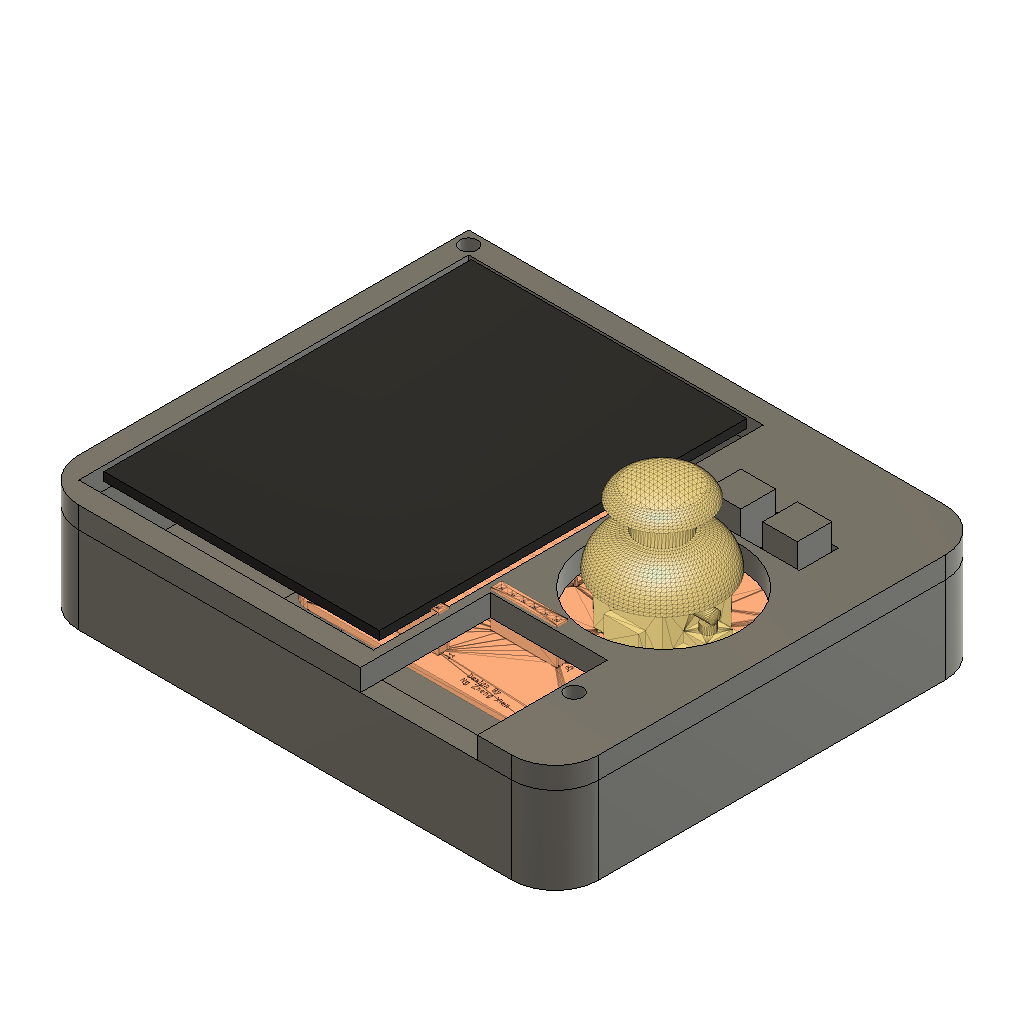
LastBraincellCase (Autodesk Fusion 360 design; units mm, degrees)
Autodesk Fusion 360 part; units mm, degrees
other "Base Mesh Feature1"
other "Base Mesh Feature2"
other "Modify1"
other "Modify2"
other "Modify3"
other "Modify4"
sketch "Sketch1" plane through (0, 0, 0) normal (0, 1, 0) x (1, 0, 0)
  line L0 (35.5, 33.5) -> (-32.6, 33.5)
  line L1 (-32.6, 33.5) -> (-32.6, -35)
  line L2 (-32.6, -35) -> (35.5, -35)
  line L3 (35.5, -35) -> (35.5, 33.5)
  line L4 (40.5, 38.5) -> (-37.6, 38.5)
  line L5 (-37.6, 38.5) -> (-37.6, -40)
  line L6 (-37.6, -40) -> (40.5, -40)
  line L7 (40.5, -40) -> (40.5, 38.5)
  line L8 (40.5, 38.5) -> (-37.6, -40) construction
  line L9 (-37.6, 38.5) -> (40.5, -40) construction
  circle A0 centre (-27.2012, -30.2516) radius 1.7516
  circle A1 centre (-27.2012, -30.2516) radius 2
  line L10 (-32.6, -35) -> (-24.6, -35)
  line L11 (-24.6, -35) -> (-24.6, -27)
  line L12 (-24.6, -27) -> (-32.6, -27)
  line L13 (-32.6, -27) -> (-32.6, -35)
  circle A2 centre (29.796, 15.5463) radius 1.7537
  circle A3 centre (29.796, 15.5463) radius 2
  line L14 (35.5, 19.9163) -> (25.5, 19.9163)
  line L15 (25.5, 19.9163) -> (25.5, 11.9163)
  line L16 (25.5, 11.9163) -> (35.5, 11.9163)
  line L17 (35.5, 11.9163) -> (35.5, 19.9163)
  line L18 (35.5, -35) -> (25.5, -35)
  line L19 (25.5, -35) -> (25.5, -27)
  line L20 (25.5, -27) -> (35.5, -27)
  line L21 (35.5, -27) -> (35.5, -35)
  circle A4 centre (29.6047, -30.2676) radius 1.7586
  circle A5 centre (29.6047, -30.2676) radius 2
  point P0 (1.45, -0.75)
  dimension "d1" = 78.1
  dimension "d2" = 78.5
  dimension "d3" = 4
  dimension "d4" = 8
  dimension "d5" = 8
  dimension "d6" = 4
  dimension "d7" = 10
  dimension "d8" = 8
  dimension "d9" = 10
  dimension "d10" = 8
  dimension "d11" = 4
  constraint horizontal L0
  constraint vertical L1
  constraint horizontal L2
  constraint vertical L3
  constraint horizontal L4
  constraint perpendicular L4 L5
  constraint parallel L4 L6
  constraint parallel L5 L7
  constraint coincident L8 P0
  constraint coincident L9 P0
  constraint concentric A0 A1
  constraint horizontal L10
  constraint vertical L11
  constraint horizontal L12
  constraint vertical L13
  constraint concentric A2 A3
  constraint horizontal L14
  constraint vertical L15
  constraint horizontal L16
  constraint vertical L17
  constraint coincident L3 L14.start
  constraint horizontal L18
  constraint vertical L19
  constraint horizontal L20
  constraint vertical L21
  constraint concentric A4 A5
  measures "d1" distance of L5.end L6.end
  measures "d2" distance of L4.end L5.end
  measures "d3" diameter of A1
  measures "d4" distance of L1.end L10.end
  measures "d5" distance of L1.end L12.end
  measures "d6" diameter of A3
  measures "d7" distance of L14.start L14.end
  measures "d8" distance of L14.start L16.end
  measures "d9" distance of L2.end L18.end
  measures "d10" distance of L2.end L20.end
  measures "d11" diameter of A5
other "Modify5"
other "Modify6"
combine "Combine1" [no effect]
sketch "Sketch2" plane through (0, 0, 0) normal (0, 1, 0) x (1, 0, 0)
  line L0 (156.8, 42.4) -> (93.2, 42.4)
  line L1 (93.2, 42.4) -> (93.2, -42.4)
  line L2 (93.2, -42.4) -> (156.8, -42.4)
  line L3 (156.8, -42.4) -> (156.8, 42.4)
  line L4 (156.8, 42.4) -> (93.2, -42.4) construction
  line L5 (93.2, 42.4) -> (156.8, -42.4) construction
  point P0 (125, 0)
  dimension "d20" = 63.6
  dimension "d21" = 84.8
  constraint horizontal L0
  constraint perpendicular L0 L1
  constraint parallel L0 L2
  constraint parallel L1 L3
  constraint coincident L4 P0
  constraint coincident L5 P0
  measures "d20" distance of L1.end L2.end
  measures "d21" distance of L0.end L1.end
extrude "Extrude5" add sketch "Sketch2" along normal blind 2 makes body 1
move_body "Move1" bodies 1 to x (1, 0, 0) y (0, 1, 0) z (0, 0, 1) at (-160, 20, 0)
sketch "Sketch3" plane through (0, 0, 0) normal (0, 1, 0) x (1, 0, 0)
  line L0 (-70, 45) -> (40, 45)
  line L1 (40, 45) -> (40, -45)
  line L2 (40, -45) -> (-70, -45)
  line L3 (-70, -45) -> (-70, 45)
  line L4 (45, 50) -> (-75, 50)
  line L5 (-75, 50) -> (-75, -50)
  line L6 (-75, -50) -> (45, -50)
  line L7 (45, -50) -> (45, 50)
  line L8 (45, 50) -> (-75, -50) construction
  line L9 (-75, 50) -> (45, -50) construction
  point P0 (-15, 0)
  dimension "d24" = 120
  dimension "d25" = 100
  constraint horizontal L0
  constraint vertical L1
  constraint horizontal L2
  constraint vertical L3
  constraint horizontal L4
  constraint perpendicular L4 L5
  constraint parallel L4 L6
  constraint parallel L5 L7
  constraint coincident L8 P0
  constraint coincident L9 P0
  measures "d24" distance of L5.end L6.end
  measures "d25" distance of L4.end L5.end
extrude "Extrude6" add sketch "Sketch3" along normal blind 15 separate body makes body 2
extrude "Extrude7" add sketch "Sketch1" along normal blind 10 separate body contours L3 L14 L15 L16 L17 | L1 L2 L10 L11 L12 L13 | L2 L3 L18 L19 L20 L21 makes body 3 at (31.6022, 6.6667, 30.3673) makes body 4 at (-25.2037, 6.6667, 30.3513) makes body 5 at (31.7935, 6.6667, -15.4466)
extrude "Extrude8" add sketch "Sketch3" against normal blind 5 contours L0 L1 L2 L3 | L4 L5 L6 L7 bodies 2 3 4 5
fillet "Fillet1" radius 5 4 edges at (30.5, 0, -11.9163) (25.5, 0, -15.9163) (30.5, 0, -19.9163) (35.5, 0, -15.9163) on bodies 2
fillet "Fillet2" radius 5 4 edges at (30.5, 0, 27) (25.5, 0, 31) (30.5, 0, 35) (35.5, 0, 31) on bodies 2
fillet "Fillet3" radius 5 4 edges at (-24.6, 0, 31) (-28.6, 0, 35) (-28.6, 0, 27) (-32.6, 0, 31) on bodies 2
sketch "Sketch4" plane through (0, 15, 0) normal (0, 1, 0) x (-1, 0, 0)
  line L0 (-40, 45) -> (70, 45)
  line L1 (70, 45) -> (70, -45)
  line L2 (70, -45) -> (-40, -45)
  line L3 (-40, -45) -> (-40, 45)
  line L4 (-45, 50) -> (-45, -50)
  line L5 (-45, -50) -> (75, -50)
  line L6 (75, -50) -> (75, 50)
  line L7 (75, 50) -> (-45, 50)
  line L8 (-8.2831, -20.073) -> (-31.2831, -20.073)
  line L9 (-31.2831, -20.073) -> (-31.2831, -29.073)
  line L10 (-31.2831, -29.073) -> (-8.2831, -29.073)
  line L11 (-8.2831, -29.073) -> (-8.2831, -20.073)
  line L12 (-8.2831, -20.073) -> (-31.2831, -29.073) construction
  line L13 (-31.2831, -20.073) -> (-8.2831, -29.073) construction
  circle A0 centre (-19, -1) radius 17.5
  line L14 (0, -45) -> (70, -45)
  line L15 (70, -45) -> (70, 45)
  line L16 (70, 45) -> (0, 45)
  line L17 (0, 45) -> (0, -45)
  line L18 (0, -45) -> (70, 45) construction
  line L19 (70, -45) -> (0, 45) construction
  line L20 (-10.7265, -22.122) -> (-15.7265, -22.122)
  line L21 (-15.7265, -22.122) -> (-15.7265, -27.122)
  line L22 (-15.7265, -27.122) -> (-10.7265, -27.122)
  line L23 (-10.7265, -27.122) -> (-10.7265, -22.122)
  line L24 (-10.7265, -22.122) -> (-15.7265, -27.122) construction
  line L25 (-15.7265, -22.122) -> (-10.7265, -27.122) construction
  line L26 (-17.2265, -28.622) -> (-9.2265, -28.622)
  line L27 (-9.2265, -28.622) -> (-9.2265, -20.622)
  line L28 (-9.2265, -20.622) -> (-17.2265, -20.622)
  line L29 (-17.2265, -20.622) -> (-17.2265, -28.622)
  line L30 (-17.2265, -28.622) -> (-9.2265, -20.622) construction
  line L31 (-9.2265, -28.622) -> (-17.2265, -20.622) construction
  line L32 (-17.2265, -28.622) -> (-6.5405, -28.622)
  line L33 (-6.5405, -28.622) -> (-6.5405, -20.622)
  line L34 (-6.5405, -20.622) -> (-17.2265, -20.622)
  line L35 (-17.2265, -20.622) -> (-17.2265, -28.622)
  line L36 (-28.7819, -27.0808) -> (-23.7819, -27.0808)
  line L37 (-23.7819, -27.0808) -> (-23.7819, -22.0808)
  line L38 (-23.7819, -22.0808) -> (-28.7819, -22.0808)
  line L39 (-28.7819, -22.0808) -> (-28.7819, -27.0808)
  line L40 (-28.7819, -27.0808) -> (-23.7819, -22.0808) construction
  line L41 (-23.7819, -27.0808) -> (-28.7819, -22.0808) construction
  line L42 (-30.2819, -28.5808) -> (-22.2819, -28.5808)
  line L43 (-22.2819, -28.5808) -> (-22.2819, -20.5808)
  line L44 (-22.2819, -20.5808) -> (-30.2819, -20.5808)
  line L45 (-30.2819, -20.5808) -> (-30.2819, -28.5808)
  line L46 (-30.2819, -28.5808) -> (-22.2819, -20.5808) construction
  line L47 (-22.2819, -28.5808) -> (-30.2819, -20.5808) construction
  line L48 (-22.2819, -28.5808) -> (-32.6542, -28.5808)
  line L49 (-32.6542, -28.5808) -> (-32.6542, -20.5808)
  line L50 (-32.6542, -20.5808) -> (-22.2819, -20.5808)
  line L51 (-22.2819, -20.5808) -> (-22.2819, -28.5808)
  point P0 (-19.7831, -24.573)
  point P1 (35, 0)
  point P2 (-13.2265, -24.622)
  point P3 (-13.2265, -24.622)
  point P4 (-26.2819, -24.5808)
  point P5 (-26.2819, -24.5808)
  dimension "d38" = 23
  dimension "d39" = 9
  dimension "d40" = 35
  dimension "d43" = 5
  dimension "d44" = 5
  dimension "d45" = 8
  dimension "d46" = 8
  dimension "d47" = 8
  dimension "d48" = 5
  dimension "d49" = 5
  dimension "d50" = 8
  dimension "d51" = 8
  dimension "d52" = 8
  constraint horizontal L8
  constraint perpendicular L8 L9
  constraint parallel L8 L10
  constraint parallel L9 L11
  constraint coincident L12 P0
  constraint coincident L13 P0
  constraint horizontal L14
  constraint perpendicular L14 L15
  constraint parallel L14 L16
  constraint parallel L15 L17
  constraint coincident L18 P1
  constraint coincident L19 P1
  constraint coincident L2 L14.start
  constraint horizontal L20
  constraint perpendicular L20 L21
  constraint parallel L20 L22
  constraint parallel L21 L23
  constraint coincident L24 P3
  constraint coincident L25 P3
  constraint horizontal L26
  constraint perpendicular L26 L27
  constraint parallel L26 L28
  constraint parallel L27 L29
  constraint coincident L30 P3
  constraint coincident L31 P3
  constraint coincident P3 P2
  constraint horizontal L32
  constraint vertical L33
  constraint horizontal L34
  constraint vertical L35
  constraint horizontal L36
  constraint perpendicular L36 L37
  constraint parallel L36 L38
  constraint parallel L37 L39
  constraint coincident L40 P5
  constraint coincident L41 P5
  constraint horizontal L42
  constraint perpendicular L42 L43
  constraint parallel L42 L44
  constraint parallel L43 L45
  constraint coincident L46 P5
  constraint coincident L47 P5
  constraint coincident P5 P4
  constraint horizontal L48
  constraint vertical L49
  constraint horizontal L50
  constraint vertical L51
  measures "d38" distance of L9.end L10.end
  measures "d39" distance of L8.end L9.end
  measures "d40" diameter of A0
  measures "d43" distance of L21.end L22.end
  measures "d44" distance of L20.end L21.end
  measures "d45" distance of L27.end L28.end
  measures "d46" distance of L26.end L27.end
  measures "d47" distance of L26.start L28.end
  measures "d48" distance of L37.end L38.end
  measures "d49" distance of L36.end L37.end
  measures "d50" distance of L43.end L44.end
  measures "d51" distance of L42.end L43.end
  measures "d52" distance of L42.end L43.end
extrude "Extrude9" add sketch "Sketch4" along normal blind 5 separate body contours L0 L2 L3 L17 | L4 L5 L6 L7 | L11 L32 L33 L34 | L9 L48 L49 L50 makes body 6
extrude "Extrude10" add sketch "Sketch4" along normal blind 2 contours L11 L27 L32 L34 | L9 L45 L48 L50 bodies 6
extrude "Extrude11" add sketch "Sketch4" along normal blind 10 contours L26 L27 L28 L29 L32 L34 L35 | L42 L43 L44 L45 L48 L50 L51 | L20 L21 L22 L23 | L36 L37 L38 L39 bodies 6
fillet "Fillet4" radius 10 2 edges at (45, 5, 50) (45, 17.5, 50) on bodies 2 6
fillet "Fillet5" radius 10 2 edges at (45, 5, -50) (45, 17.5, -50) on bodies 2 6
fillet "Fillet7" radius 10 2 edges at (-75, 5, 50) (-75, 17.5, 50) on bodies 2 6
extrude "Extrude12" add 1 faces at (0, 16.6667, 15) along direction (-1, 0, 0) blind 2 separate body on bodies 6 makes body 7
combine "Combine2" operation add target body 6 tool bodies 7
extrude "Extrude13" cut 1 faces at (29.3611, 0, 31.0869) along direction (0, 1, 0) blind 40 on bodies 2 bodies 6
sketch "Sketch5" plane through (0, 0, 0) normal (0, 1, 0) x (1, 0, 0)
  circle A0 centre (-72, 47) radius 2
  dimension "d69" = 4
  measures "d69" diameter of A0
extrude "Extrude14" cut sketch "Sketch5" along normal blind 20 bodies 2 6
extrude "Extrude15" cut 1 faces at (-72.8806, 0, -46.5172) along direction (0, -1, 0) blind 10 on bodies 2 bodies 2
sketch "Sketch6" plane through (0, 0, 50) normal (0, 0, 1) x (1, 0, 0)
  line L0 (-65, 15) -> (-65, -5)
  line L1 (-65, -5) -> (35, -5)
  line L2 (35, -5) -> (35, 15)
  line L3 (35, 15) -> (-65, 15)
  line L4 (0, 13.5) -> (27, 13.5)
  line L5 (27, 13.5) -> (27, 20.5)
  line L6 (27, 20.5) -> (0, 20.5)
  line L7 (0, 20.5) -> (0, 13.5)
  dimension "d74" = 27
  dimension "d75" = 7
  constraint horizontal L4
  constraint vertical L5
  constraint horizontal L6
  constraint vertical L7
  measures "d74" distance of L4.start L4.end
  measures "d75" distance of L4.start L6.end
extrude "Extrude16" cut sketch "Sketch6" against normal blind 25 contours L3 L5 L6 L7 bodies 6
extrude "Extrude17" cut 1 faces at (9, 16.6667, 25) along direction (0, 0, -1) blind 5 on bodies 6 bodies 6
equation "d1 = 68.100 mm + 10 mm"
equation "d2 = 68.500 mm + 10 mm"
equation "d24 = 110.000 mm + 10 mm"
equation "d25 = 90.000 mm + 10 mm"
